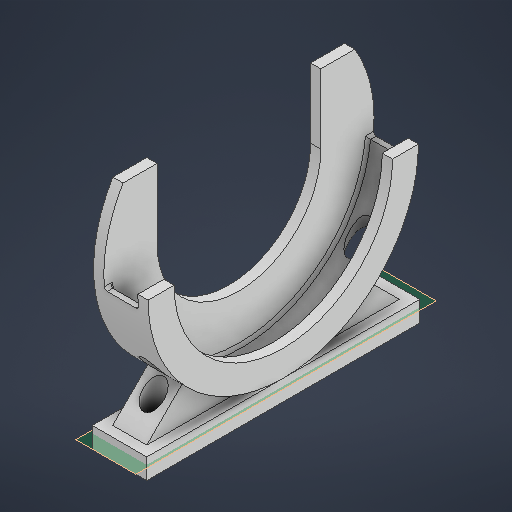
# Autodesk Inventor part: 패드 거치대
Saved by Autodesk Inventor 2027 (Build 310192000, 192)
## iProperties
Created: 2026-10-07
Part Number: 패드 거치대
Material: 일반
Document SubType Name: Modeling
Designer: bingo
Density: 1 g/cm^3
Appearance: 기본값
Author: bingo
Autodesk Inventor part; units mm, degrees
ref_plane "YZ Plane" through (0, 0, 0) normal (1, 0, 0) x (0, 1, 0)
ref_plane "XZ Plane" through (0, 0, 0) normal (0, 1, 0) x (-1, 0, 0)
ref_plane "XY Plane" through (0, 0, 0) normal (0, 0, 1) x (1, 0, 0)
sketch "스케치1" plane through (0, 0, 0) normal (0, 1, 0) x (-1, 0, 0)
  line L0 (20, 100) -> (-20, 100)
  line L1 (-20, 100) -> (-20, -100)
  line L2 (-20, -100) -> (20, -100)
  line L3 (20, -100) -> (20, 100)
  line L4 (0, 55.9786) -> (0, 0)
  line L5 (0, 0) -> (54.5117, 0)
  dimension "d0" = 200
  dimension "d2" = 40
  constraints: 12 end point, 2 parallel, 2 perpendicular, 1 horizontal, 1 vertical, 2 other
  measures "d0" distance of L2.end L0.start
  measures "d2" distance of L1.end L2.end
extrude "돌출1" add sketch "스케치1" along normal blind 15
sketch "스케치2" plane through (0, 0, 0) normal (1, 0, 0) x (0, 1, 0)
  circle A0 centre (114, 0) radius 99
  line L0 (15, 100) -> (15, -100) projected
  line L1 (0, 100) -> (0, -100) projected
  point P0 (0, 0)
  point P1 (0, 0)
  dimension "d5" = 198
  constraints: 1 centre point, 1 horizontal alignment, 1 midpoint, 1 tangent
  measures "d5" diameter of A0
extrude "돌출2" add sketch "스케치2" along normal mid plane 40
sketch "스케치5" plane through (0, 0, 0) normal (1, 0, 0) x (0, 1, 0)
  line L0 (15, 0) -> (15, -100) projected
  line L1 (15, -92.5) -> (45, -62.5)
  line L2 (45, -62.5) -> (45, 62.5)
  line L3 (45, 62.5) -> (15, 92.5)
  line L4 (15, 92.5) -> (15, -92.5)
  line L5 (0, 0) -> (203.8358, 0)
  dimension "d14" = 30
  dimension "d15" = 185
  constraints: 10 end point, 2 parallel, 1 horizontal, 1 perpendicular, 1 point on line, 1 other
  measures "d14" distance between parallel lines of L0 L2
  measures "d15" distance of L3.end L1.start
sketch "스케치3" plane through (20, 114, 0) normal (1, 0, 0) x (0, 0, -1)
  line L0 (-137.2667, 51) -> (150.2914, 51)
  line L1 (150.2914, 51) -> (150.2914, 104.0367)
  line L2 (150.2914, 104.0367) -> (-137.2667, 104.0367)
  line L3 (-137.2667, 104.0367) -> (-137.2667, 51)
  line L4 (0, -99) -> (100, -99) projected
  point P0 (0, -114)
  dimension "d8" = 150
  constraints: 8 end point, 2 parallel, 1 horizontal, 1 perpendicular
  measures "d8" distance between parallel lines of L4 L0
extrude "돌출3" cut sketch "스케치3" against normal through all
extrude "돌출5" add sketch "스케치5" along normal mid plane 25
sketch "스케치4" plane through (0, 0, 0) normal (1, 0, 0) x (0, 1, 0)
  circle A0 centre (114, 0) radius 95
  arc A1 (15, 0) -> (165, -84.8528) centre (114, 0) ccw projected
  point P0 (0, 0)
  dimension "d11" = 190
  constraints: 1 centre point, 1 concentric
  measures "d11" diameter of A0
extrude "돌출4" cut sketch "스케치4" along normal mid plane 25
sketch "스케치6" plane through (20, 0, 0) normal (1, 0, 0) x (0, 0, -1)
  arc A0 (0, 15) -> (84.8528, 165) centre (0, 114) ccw projected
  circle A1 centre (0, 114) radius 80
  point P0 (0, 0)
  dimension "d18" = 160
  constraints: 1 centre point, 1 concentric
  measures "d18" diameter of A1
extrude "돌출6" cut sketch "스케치6" against normal blind 25
sketch "스케치7" plane through (0, 0, 0) normal (1, 0, 0) x (0, 1, 0)
  line L0 (202.3844, 153.7005) -> (104, 153.7005)
  line L1 (104, 153.7005) -> (104, -164.587)
  line L2 (104, -164.587) -> (202.3844, -164.587)
  line L3 (202.3844, -164.587) -> (202.3844, 153.7005)
  line L4 (15, 0) -> (15, -100) projected
  arc A0 (165, 61.636) -> (165, -61.636) centre (114, 0) ccw projected
  point P0 (0, 0)
  dimension "d22" = 10
  constraints: 8 end point, 2 parallel, 1 horizontal, 1 perpendicular
  measures "d22" distance from line of L1 A0.centre
extrude "돌출7" cut sketch "스케치7" along normal mid plane 25 contours L3 L2 L1 L0
ref_plane "작업 평면1" through (0, 10, 0) normal (0, -1, 0) x (1, 0, 0)
sketch "스케치8" plane through (0, 10, 0) normal (0, -1, 0) x (1, 0, 0)
  circle A0 centre (0, 75) radius 7.5
  circle A1 centre (0, -75) radius 7.5
  line L0 (0, 73.1812) -> (0, -57.923)
  line L1 (0, 0) -> (-87.0922, 0)
  dimension "d26" = 15
  dimension "d27" = 150
  constraints: 4 end point, 3 point on line, 2 centre point, 1 equal radius, 1 horizontal, 1 symmetric about line, 1 vertical
  measures "d26" diameter of A0
  measures "d27" distance of A1.centre A0.centre
extrude "돌출8" cut sketch "스케치8" against normal through all
sketch "스케치9" plane through (0, 10, 0) normal (0, -1, 0) x (1, 0, 0)
  circle A0 centre (0, 75) radius 5
  circle A1 centre (0, 75) radius 7.5 projected
  line L0 (0, 0) -> (-56.4637, 0)
  circle A2 centre (0, -75) radius 5
  dimension "d30" = 10
  constraints: 2 centre point, 2 end point, 1 concentric, 1 horizontal, 1 symmetric about line, 1 other
  measures "d30" diameter of A0
extrude "돌출9" cut sketch "스케치9" along normal through all contours A0 | A2
sketch "스케치10" plane through (-20, 0, 0) normal (-1, 0, 0) x (0, 0, 1)
  line L0 (60, 217.0825) -> (-60, 217.0825)
  line L1 (-60, 217.0825) -> (-60, 54)
  line L2 (-60, 54) -> (60, 54)
  line L3 (60, 54) -> (60, 217.0825)
  line L4 (0, 0) -> (0, 260.9652)
  arc A0 (0, 15) -> (84.8528, 165) centre (0, 114) ccw projected
  circle A1 centre (0, 114) radius 60
  point P0 (-60, 114)
  point P1 (60, 114)
  dimension "d33" = 120
  dimension "d34" = 60
  constraints: 10 end point, 2 parallel, 1 centre point, 1 concentric, 1 horizontal, 1 perpendicular, 1 tangent, 1 vertical, 1 other
  measures "d33" distance of L1.end L2.end
  measures "d34" distance from line of L2 A0.centre
extrude "돌출10" cut sketch "스케치10" against normal blind 10 contours L3 A1 L4 L0 | L4 A1 L1 L0 | A1 L4 | L4 A1
sketch "스케치11" plane through (20, 0, 0) normal (1, 0, 0) x (0, 0, -1)
  arc A0 (0, 15) -> (84.8528, 165) centre (0, 114) ccw projected
  line L0 (-224.0953, 213.6856) -> (176.2792, 213.6856)
  line L1 (176.2792, 213.6856) -> (176.2792, 114)
  line L2 (176.2792, 114) -> (-224.0953, 114)
  line L3 (-224.0953, 114) -> (-224.0953, 213.6856)
  point P0 (0, 0)
  constraints: 8 end point, 2 parallel, 1 horizontal, 1 perpendicular, 1 point on line
extrude "돌출11" cut sketch "스케치11" against normal blind 10
fillet "모깎기1" radius 2 6 edges at (-12.5, 19, 0) (-12.5, 104, 96.4829) (-12.5, 104, -96.4829) (12.5, 104, -96.4829) (12.5, 104, 96.4829) (12.5, 19, 0)
